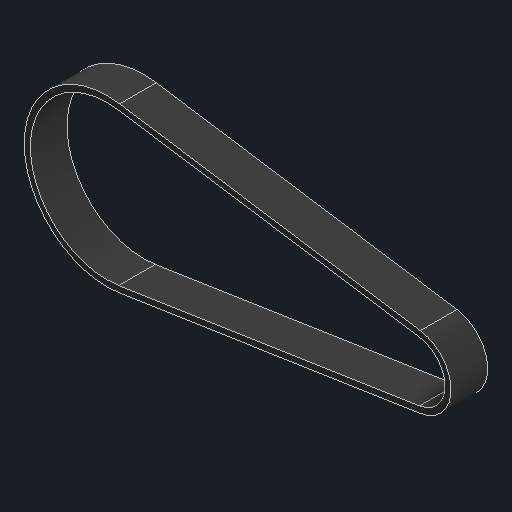
# Autodesk Inventor part: gt2_belt_6mm_158
Saved by Autodesk Inventor 2027.1 (Build 311270010, 270A)
## iProperties
Created: 2026-11-04
Part Number: gt2_belt_6mm_158
Material: Generic
Description: GT2 closed loop belt, 6 mm wide, 158 mm (shown on 40T/16T at 50.42 mm centres)
Document SubType Name: Modeling
Designer: Claude (from photos)
Density: 1 g/cm^3
Appearance: Rubber - Black
Author: alexg
Autodesk Inventor part; units mm, degrees
ref_plane "YZ Plane" through (0, 0, 0) normal (1, 0, 0) x (0, 1, 0)
ref_plane "XZ Plane" through (0, 0, 0) normal (0, 1, 0) x (-1, 0, 0)
ref_plane "XY Plane" through (0, 0, 0) normal (0, 0, 1) x (1, 0, 0)
sketch "Belt loop sketch" plane through (0, 0, 0) normal (0, 0, 1) x (1, 0, 0)
  arc A0 (1.9042, 12.43) -> (1.9042, -12.43) centre (0, 0) ccw
  arc A1 (51.1681, -4.883) -> (51.1681, 4.883) centre (50.42, 0) ccw
  line L0 (1.9042, -12.43) -> (51.1681, -4.883)
  line L1 (51.1681, 4.883) -> (1.9042, 12.43)
  arc A2 (2.0556, 13.4185) -> (2.0556, -13.4185) centre (0, 0) ccw
  arc A3 (51.3195, -5.8715) -> (51.3195, 5.8715) centre (50.42, 0) ccw
  line L2 (2.0556, -13.4185) -> (51.3195, -5.8715)
  line L3 (51.3195, 5.8715) -> (2.0556, 13.4185)
  constraints: 8 end point, 8 point on circle, 4 centre point
extrude "Belt loop" add sketch "Belt loop sketch" along normal blind 6
body "Solid1"
